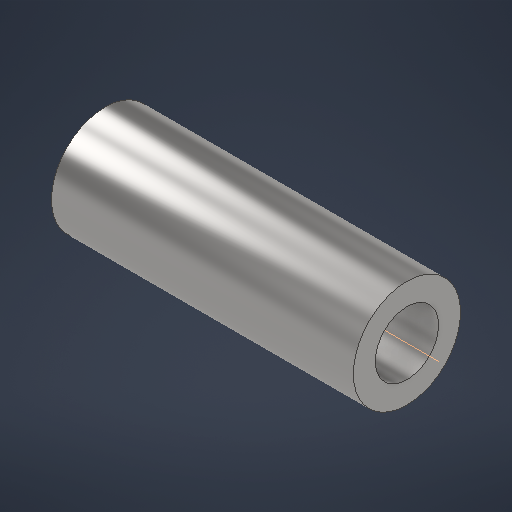
# Autodesk Inventor part: Wrist_Pin
Saved by Autodesk Inventor 2027.1 (Build 311270010, 270A)
## iProperties
Created: 2026-10-17
Part Number: Wrist_Pin
Material: Steel, Alloy
Document SubType Name: Modeling
Designer: kashyap
Density: 7.73 g/cm^3
Appearance: Semi-Polished
Mass: 118.569 g
Surface Area: 73.1206 cm^2
Volume: 15.3388 cm^3
Material_Status: Assumed for this reconstruction
Author: kashyap
Autodesk Inventor part; units mm, degrees
derived "V6_Engine_Master.ipt"
sketch "SK_Pin" plane through (0, 0, 0) normal (1, 0, 0) x (0, 1, 0)
  circle A0 centre (0, 0) radius 11
  circle A1 centre (0, 0) radius 6.5
  dimension "d19" = 22
  dimension "d20" = 13
  constraints: 2 centre point
  measures "d19" diameter of A0
  measures "d20" diameter of A1
extrude "Pin_Body" add sketch "SK_Pin" along normal mid plane 62
ref_plane "Pin_Mid_Plane" through (0, 0, 0) normal (1, 0, 0) x (0, 1, 0)
equation "\"d19\" = Pin_Diameter"
equation "\"d20\" = Pin_ID"
equation "\"d21\" = Pin_Length"
equation "\"Pin_Diameter\" = 22"
equation "\"Pin_ID\" = 13"
equation "\"Pin_Length\" = 62"
body "Solid1"
